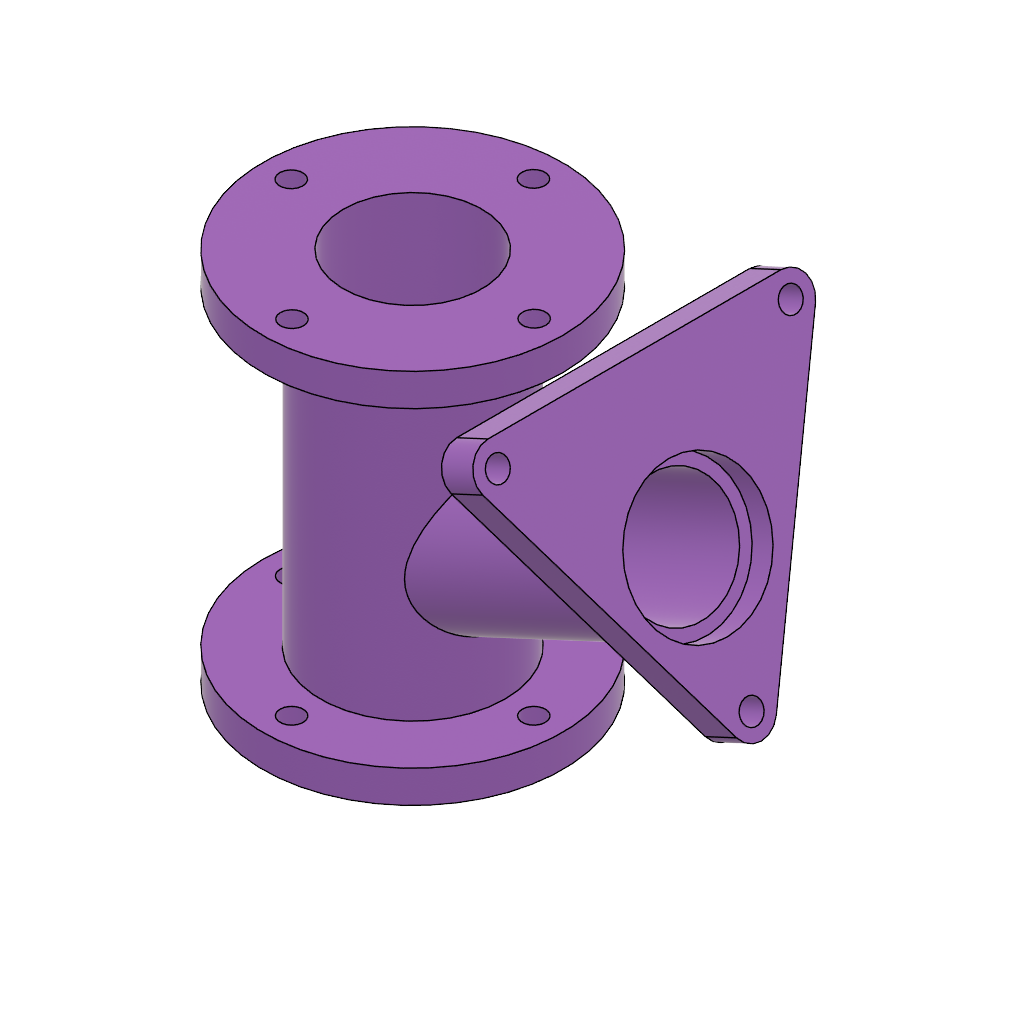
level -2 task 4 (Autodesk Fusion 360 design; units mm, degrees)
part number: 2026-10-11-16-59-34-654
Autodesk Fusion 360 part; units mm, degrees
sketch "Sketch1" plane through (0, 0, 0) normal (0, 1, 0) x (1, 0, 0)
sketch "Sketch2" plane through (0, 0, 0) normal (0, 0, 1) x (1, 0, 0)
  line L0 (0, 0) -> (0, 163)
  line L1 (0, 0) -> (0, 55)
  line L2 (0, 55) -> (115.1011, 108.6725)
  line L3 (0, 55) -> (127, 55) construction
  dimension "d1" = 163
  dimension "d2" = 55
  dimension "d5" = 127
  dimension "d6" = 25
  constraint coincident L0.start L1.start
  constraint vertical L0
  constraint vertical L1
  constraint horizontal L3
  measures "d1" distance of L0.start L0.end
  measures "d2" distance of L0.start L1.end
  measures "d5" distance of L1.end L2.end
  measures "d6" angle of L2 L3
sketch "Sketch3" plane through (0, 0, 0) normal (0, 1, 0) x (1, 0, 0)
  circle A0 centre (0, 0) radius 30
  circle A1 centre (0, 0) radius 40
  circle A2 centre (0, 0) radius 65
  circle A3 centre (0, 0) radius 52.5
  circle A4 centre (0, 0) radius 5
  circle A5 centre (52.5, 0) radius 5
  circle A6 centre (52.5, 0) radius 5
  circle A7 centre (0, 52.5) radius 5
  circle A8 centre (-52.5, 0) radius 5
  circle A9 centre (0, -52.5) radius 5
  dimension "d7" = 60
  dimension "d8" = 80
  dimension "d9" = 130
  dimension "d10" = 105
  dimension "d11" = 10
  dimension "d12" = 10
  dimension "d13" = 10
  dimension "d15" = 360
  constraint coincident A0.centre A1.centre
  constraint concentric A0 A1
  constraint concentric A0 A2
  constraint concentric A1 A3
  constraint concentric A0 A4
  measures "d7" diameter of A0
  measures "d8" diameter of A1
  measures "d9" diameter of A2
  measures "d10" diameter of A3
  measures "d11" diameter of A4
  measures "d12" diameter of A5
  measures "d13" diameter of A6
extrude "Extrude1" add sketch "Sketch3" along normal blind 163 contours A1 makes body 1
extrude "Extrude2" add sketch "Sketch3" along normal blind 14 contours A2 | A3 A5 A6 A7 A8 A9 bodies 1
sketch "Sketch4" plane through (0, 163, 0) normal (0, 1, 0) x (-1, 0, 0)
  circle A0 centre (0, 0) radius 30
  circle A1 centre (0, 0) radius 40
  circle A2 centre (0, 0) radius 65
  circle A3 centre (0, 0) radius 52.5
  circle A4 centre (-52.4997, -0.1626) radius 5
  circle A5 centre (0.1626, -52.4997) radius 5
  circle A6 centre (52.4997, 0.1626) radius 5
  circle A7 centre (-0.1626, 52.4997) radius 5
  dimension "d20" = 25
  dimension "d21" = 12.5
  dimension "d22" = 10
  dimension "d24" = 360
  constraint coincident A3 A4.centre
  measures "d22" diameter of A4
extrude "Extrude3" add sketch "Sketch4" against normal blind 14 contours A2 | A3 A4 A5 A6 A7 bodies 1
sketch "Sketch5" plane through (0, 0, 0) normal (0, 0, 1) x (1, 0, 0)
ref_plane "WorkPlane2" through (114.5874, 108.433, 0) normal (0.906308, 0.422618, 0) x (0, 0, 1)
sketch "Sketch6" plane through (114.5874, 108.433, 0) normal (0.906308, 0.422618, 0) x (0, 0, 1)
  line L0 (-63.4926, -65.0252) -> (63.5244, -64.9748)
  line L1 (72.1787, -49.9714) -> (8.6265, 60.0034)
  line L2 (-8.694, 59.9966) -> (-72.1589, -50.0286)
  circle A0 centre (0, 0) radius 30
  circle A1 centre (0, 0) radius 25
  arc A2 (63.5244, -64.9748) -> (72.1787, -49.9714) centre (63.5204, -54.9748) ccw
  arc A3 (-72.1589, -50.0286) -> (-63.4926, -65.0252) centre (-63.4966, -55.0252) ccw
  arc A4 (8.6265, 60.0034) -> (-8.694, 59.9966) centre (-0.0318, 55) ccw
  circle A5 centre (-63.4966, -55.0252) radius 5
  circle A6 centre (63.5204, -54.9748) radius 5
  circle A7 centre (-0.0318, 55) radius 5
  point P0 (-80.8132, -65.0321)
  point P1 (6.986, -17.1644)
  dimension "d31" = 100
  dimension "d32" = 60
  dimension "d33" = 50
  dimension "d34" = 10
  dimension "d35" = 10
  dimension "d36" = 10
  dimension "d37" = 10
  constraint coincident A0.centre A1.centre
  constraint tangent L0 A2
  constraint tangent L1 A2
  constraint coincident P0 L0
  constraint coincident P0 L2
  constraint tangent L0 A3
  constraint tangent L2 A3
  constraint equal A2 A3
  constraint tangent L2 A4
  constraint tangent L1 A4
  constraint equal A2 A4
  constraint concentric A3 A5
  constraint concentric A2 A6
  constraint concentric A4 A7
  measures "d31" distance of P0 P1
  measures "d32" diameter of A0
  measures "d33" diameter of A1
  measures "d34" radius of A2
  measures "d35" diameter of A5
  measures "d36" diameter of A6
  measures "d37" diameter of A7
extrude "Extrude4" add sketch "Sketch6" along normal up to surface contours A0 end surface at (39.8012, 104, -3.9827) on bodies 1 bodies 1
extrude "Extrude5" add sketch "Sketch6" along normal blind 10 separate body contours L0 L1 L2 A2 A3 A4 makes body 2
extrude "Extrude6" add sketch "Sketch6" against normal blind 5 contours L0 L1 L2 A2 A3 A4 bodies 1 2
